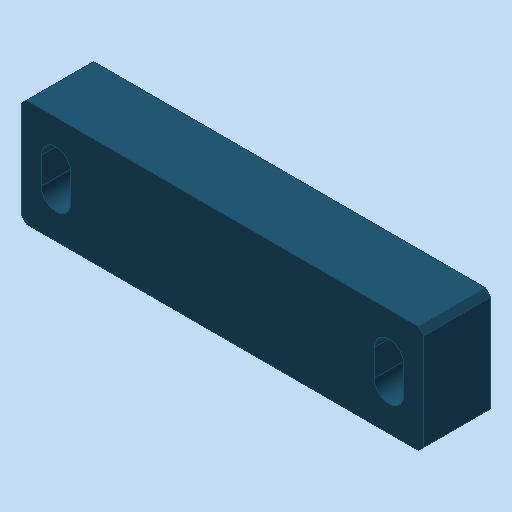
# Autodesk Inventor part: MM0868AN100_G80_111
Saved by Autodesk Inventor 2023.3 (Build 273359000, 359)
## iProperties
RuleStatus: InUse
Created: 2020-12-08
Part Number: MM0868AN100_G80_111
Material: 3.3547 AlMg4,5Mn0,7 - AW 5083
Description: =<RBPARTNOTITLE2>
Document SubType Name: Modeling
Designer: RUD
Mass: 376.781 g
Surface Area: 232.746 cm^2
Volume: 139.548 cm^3
Density: 2.7 g/cm^3
Appearance: Cyangr-D
AnP_Kategorie: 1
AnP_Material: =<Material>
AnP_TemplVers: 20200821
RBDOCUMENTTYPE: DRF
RBDOCUMENTVERSION: 00
RBDRAWINGMAINSCALE: 1:1
RBDRAWINGMISSINGSPEC: --
RBDRAWINGVOLUME: --
RBDSV1: 0850
RBGBEDGESIN1: +0,5
RBGBEDGESIN2: +0,2
RBGBEDGESOUT1: -0,3
RBGBEDGESOUT2: -0,1
RBMATERIAL: =<Material>
RBMATMEETS: --
RBMATNO: =<Part Number>
RBPARTMADEOF: Fl.40x25x153
RBPARTNO: SIEHE MNR
RBPARTNOTITLE1: manufactured part
RBPARTNOTITLE2: Anfertigungsteil
RBPARTSAFETYINDICATOR: --
RBSURFACE: anodised colourless
RBSURFACE2: eloxiert farblos
RBZEDGESNORM: ISO13715:2002-06
RBZGENDIMCLASS: m
RBZGENDIMNORM: ISO 2768-1:1989-11
RBZGENGEOCLASS: H
RBZGENGEONORM: ISO 2768-2:1989-11
RBZSURFACENORM: ISO13D2:2002-02
RBZTOLERANCENORM: ISO 14405-1:2010-12
Author: RUD
Keywords: =<RBPARTMADEOF>
Comments: =<RBSURFACE2>
Revision Number: 01
Autodesk Inventor part; units mm, degrees
ref_plane "YZ Plane" through (0, 0, 0) normal (1, 0, 0) x (0, 1, 0)
ref_plane "XZ Plane" through (0, 0, 0) normal (0, 1, 0) x (-1, 0, 0)
ref_plane "XY Plane" through (0, 0, 0) normal (0, 0, 1) x (1, 0, 0)
sketch "Skizze1" plane through (0, 0, 0) normal (0, 0, 1) x (1, 0, 0)
  line L0 (0, 28) -> (0, -28) projected
  line L1 (-105, 0) -> (105, 0) projected
  line L2 (-75, 20) -> (75, 20)
  line L3 (75, 20) -> (75, -20)
  line L4 (75, -20) -> (-75, -20)
  line L5 (-75, -20) -> (-75, 20)
  dimension "d0" = 150
  dimension "d1" = 40
  constraints: 8 end point, 2 parallel, 1 horizontal, 1 perpendicular, 2 other
  measures "d0" distance between parallel lines of L3 L5
  measures "d1" distance between parallel lines of L4 L2
extrude "Extrusion1" add sketch "Skizze1" along normal blind 25
sketch "Skizze2" plane through (0, 0, 25) normal (0, 0, 1) x (1, 0, 0)
  line L0 (0, 28) -> (0, -28) projected
  line L1 (-105, 0) -> (105, 0) projected
  line L2 (-62, 5) -> (-62, -5) construction
  line L3 (-67.5, 5) -> (-67.5, -5)
  line L4 (-56.5, -5) -> (-56.5, 5)
  arc A0 (-56.5, 5) -> (-67.5, 5) centre (-62, 5) ccw
  arc A1 (-67.5, -5) -> (-56.5, -5) centre (-62, -5) ccw
  line L5 (62, 5) -> (62, -5) construction
  line L6 (67.5, 5) -> (67.5, -5)
  line L7 (56.5, -5) -> (56.5, 5)
  arc A2 (67.5, 5) -> (56.5, 5) centre (62, 5) ccw
  arc A3 (56.5, -5) -> (67.5, -5) centre (62, -5) ccw
  point P0 (-62, 0)
  point P1 (62, 0)
  dimension "d4" = 11
  dimension "d5" = 10
  dimension "d6" = 124
  constraints: 16 end point, 8 point on circle, 8 tangent, 4 centre point, 3 parallel, 2 midpoint, 2 point on line, 1 equal radius, 1 perpendicular, 1 symmetric about line, 1 vertical
  measures "d4" distance between parallel lines of L4 L3
  measures "d5" distance of L3.start L3.end
  measures "d6" distance between parallel lines of L5 L2
extrude "Extrusion2" cut sketch "Skizze2" against normal through all
chamfer "Fase1" distance 2 angle 45 4 edges at (-75, 20, 12.5) (-75, -20, 12.5) (75, -20, 12.5) (75, 20, 12.5)
